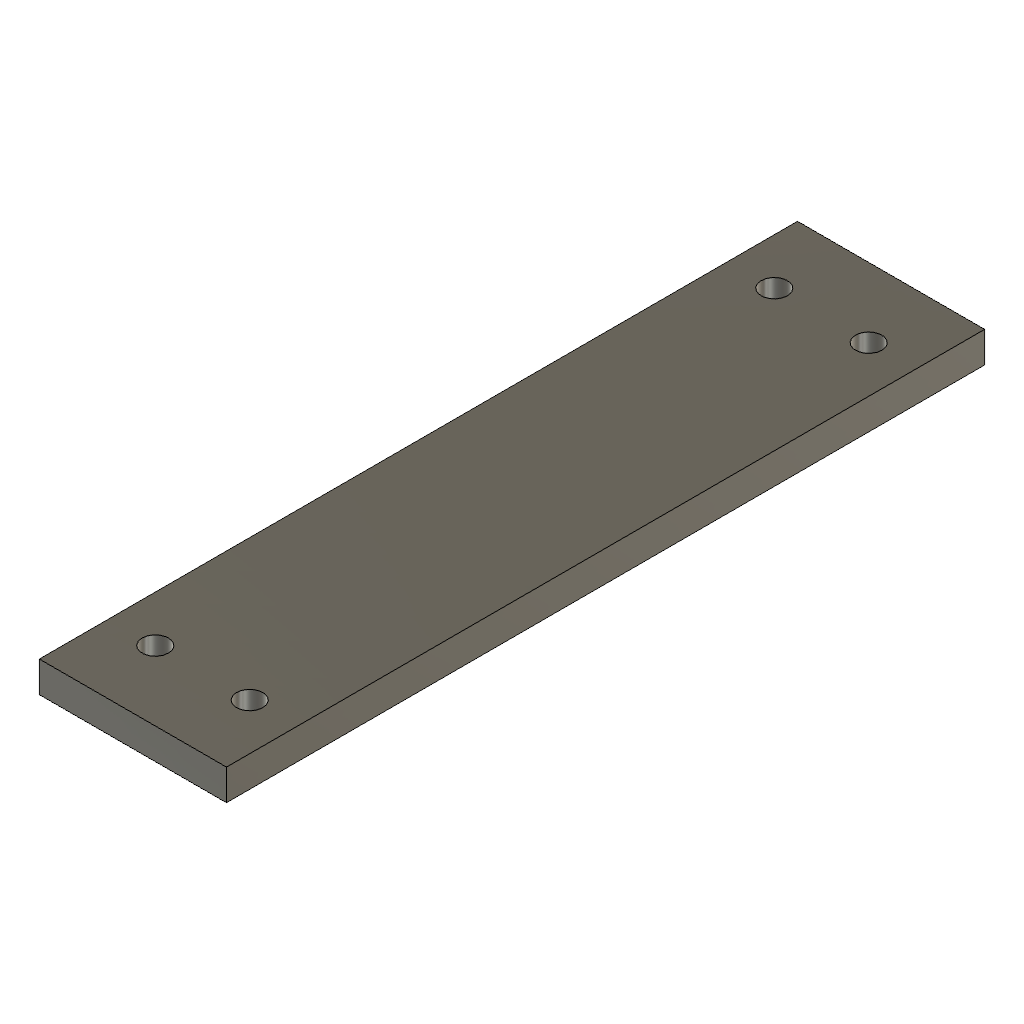
tray_bridge (Autodesk Fusion 360 design; units mm, degrees)
part number: 2026-10-11-03-14-11-683
Autodesk Fusion 360 part; units mm, degrees
sketch "Wide upper splice sketch" plane through (0, 0, 0) normal (0, 0, 1) x (1, 0, 0)
  line L0 (0, -49) -> (24.2, -49)
  line L1 (24.2, -49) -> (24.2, 49)
  line L2 (24.2, 49) -> (0, 49)
  line L3 (0, 49) -> (0, -49)
extrude "Wide upper splice" add sketch "Wide upper splice sketch" along normal blind 4
ref_plane "WorkPlane1" through (0, 0, -0.05) normal (0, 0, 1) x (1, 0, 0)
sketch "Tray splice hole (6, -40) sketch" plane through (0, 0, -0.05) normal (0, 0, 1) x (1, 0, 0)
  circle A0 centre (6, -40) radius 1.7
  dimension "d129" = 3.4
  measures "d129" diameter of A0
extrude "Tray splice hole (6, -40)" cut sketch "Tray splice hole (6, -40) sketch" along normal blind 4.1
ref_plane "WorkPlane2" through (0, 0, -0.05) normal (0, 0, 1) x (1, 0, 0)
sketch "Tray splice hole (6, 40) sketch" plane through (0, 0, -0.05) normal (0, 0, 1) x (1, 0, 0)
  circle A0 centre (6, 40) radius 1.7
  dimension "d134" = 3.4
  measures "d134" diameter of A0
extrude "Tray splice hole (6, 40)" cut sketch "Tray splice hole (6, 40) sketch" along normal blind 4.1
ref_plane "WorkPlane3" through (0, 0, -0.05) normal (0, 0, 1) x (1, 0, 0)
sketch "Tray splice hole (18.2, -40) sketch" plane through (0, 0, -0.05) normal (0, 0, 1) x (1, 0, 0)
  circle A0 centre (18.2, -40) radius 1.7
  dimension "d139" = 3.4
  measures "d139" diameter of A0
extrude "Tray splice hole (18.2, -40)" cut sketch "Tray splice hole (18.2, -40) sketch" along normal blind 4.1
ref_plane "WorkPlane4" through (0, 0, -0.05) normal (0, 0, 1) x (1, 0, 0)
sketch "Tray splice hole (18.2, 40) sketch" plane through (0, 0, -0.05) normal (0, 0, 1) x (1, 0, 0)
  circle A0 centre (18.2, 40) radius 1.7
  dimension "d144" = 3.4
  measures "d144" diameter of A0
extrude "Tray splice hole (18.2, 40)" cut sketch "Tray splice hole (18.2, 40) sketch" along normal blind 4.1
equation "d125 = bridgeThickness"
equation "d129 = m3Clearance"
equation "d134 = m3Clearance"
equation "d139 = m3Clearance"
equation "d144 = m3Clearance"
equation "m3Clearance = 3.4 mm" comment "Weighted stand"
equation "bridgeThickness = 4 mm" comment "Weighted stand"
named bodies: "tray_bridge native printable solid"
